Autodesk Inventor part; units mm, degrees
(part 2 of 2)
  line L877 (-195.7056, 63.0085) -> (-199.6927, 63.0085)
  line L878 (-201.2028, 81.1379) -> (-201.786, 81.1151)
  line L879 (-201.786, 81.1151) -> (-202.2096, 81.0461)
  line L880 (-202.2096, 81.0461) -> (-202.5152, 80.9103)
  line L881 (-202.5152, 80.9103) -> (-202.7369, 80.6784)
  line L882 (-202.7369, 80.6784) -> (-202.8877, 80.344)
  line L883 (-202.8877, 80.344) -> (-202.9805, 79.9076)
  line L884 (-202.9805, 79.9076) -> (-203.0286, 79.3151)
  line L885 (-203.0286, 79.3151) -> (-203.0444, 78.5051)
  line L886 (-203.0444, 78.5051) -> (-203.0056, 76.7655)
  line L887 (-203.0056, 76.7655) -> (-202.8887, 74.9256)
  line L888 (-202.8887, 74.9256) -> (-202.8067, 73.9341)
  line L889 (-202.8067, 73.9341) -> (-202.7609, 73.3636)
  line L890 (-202.7609, 73.3636) -> (-213.2957, 73.3636)
  line L891 (-213.2957, 73.3636) -> (-213.2957, 77.6862)
  line L892 (-213.2957, 77.6862) -> (-206.8037, 77.6862)
  line L893 (-206.8037, 77.6862) -> (-206.8797, 78.5292)
  line L894 (-206.8797, 78.5292) -> (-206.9367, 80.0385)
  line L895 (-206.9367, 80.0385) -> (-206.9556, 81.0341)
  line L896 (-206.9556, 81.0341) -> (-206.9328, 81.7671)
  line L897 (-206.9328, 81.7671) -> (-206.7505, 83.065)
  line L898 (-206.7505, 83.065) -> (-206.3859, 84.1386)
  line L899 (-206.3859, 84.1386) -> (-205.8393, 84.9882)
  line L900 (-205.8393, 84.9882) -> (-205.4975, 85.3288)
  line L901 (-205.4975, 85.3288) -> (-205.1474, 85.5896)
  line L902 (-205.1474, 85.5896) -> (-204.3364, 85.9849)
  line L903 (-204.3364, 85.9849) -> (-203.8754, 86.1199)
  line L904 (-203.8754, 86.1199) -> (-203.3727, 86.2211)
  line L905 (-203.3727, 86.2211) -> (-202.2283, 86.3369)
  line L906 (-202.2283, 86.3369) -> (-201.5863, 86.3515)
  line L907 (-201.5863, 86.3515) -> (-200.8617, 86.3369)
  line L908 (-200.8617, 86.3369) -> (-199.5953, 86.2211)
  line L909 (-199.5953, 86.2211) -> (-199.0535, 86.1199)
  line L910 (-199.0535, 86.1199) -> (-198.5613, 85.9849)
  line L911 (-198.5613, 85.9849) -> (-197.6925, 85.5896)
  line L912 (-197.6925, 85.5896) -> (-197.3156, 85.3288)
  line L913 (-197.3156, 85.3288) -> (-196.9763, 85.0191)
  line L914 (-196.9763, 85.0191) -> (-196.4069, 84.2201)
  line L915 (-196.4069, 84.2201) -> (-196.1771, 83.7308)
  line L916 (-196.1771, 83.7308) -> (-195.9838, 83.1808)
  line L917 (-195.9838, 83.1808) -> (-195.6961, 81.8842)
  line L918 (-195.6961, 81.8842) -> (-195.6018, 81.1379)
  line L919 (-195.6018, 81.1379) -> (-201.2028, 81.1379)
  line L920 (-213.2957, 78.7608) -> (-213.2957, 85.0491)
  line L921 (-213.2957, 85.0491) -> (-209.3327, 85.0491)
  line L922 (-209.3327, 85.0491) -> (-209.3327, 78.7608)
  line L923 (-209.3327, 78.7608) -> (-213.2957, 78.7608)
  line L924 (-195.5018, 78.8368) -> (-195.5468, 77.2848)
  line L925 (-195.5468, 77.2848) -> (-195.6816, 75.7527)
  line L926 (-195.6816, 75.7527) -> (-195.8774, 74.3455)
  line L927 (-195.8774, 74.3455) -> (-196.1132, 73.1599)
  line L928 (-196.1132, 73.1599) -> (-199.7725, 73.1599)
  line L929 (-199.7725, 73.1599) -> (-199.6257, 74.5822)
  line L930 (-199.6257, 74.5822) -> (-199.458, 77.139)
  line L931 (-199.458, 77.139) -> (-199.437, 78.2735)
  line L932 (-199.437, 78.2735) -> (-199.4501, 79.3223)
  line L933 (-199.4501, 79.3223) -> (-199.4889, 80.0633)
  line L934 (-199.4889, 80.0633) -> (-195.5259, 80.0633)
  line L935 (-195.5259, 80.0633) -> (-195.508, 79.5529)
  line L936 (-195.508, 79.5529) -> (-195.5018, 78.8368)
  line L937 (-204.5026, 98.0129) -> (-206.3415, 98.006)
  line L938 (-206.3415, 98.006) -> (-207.4151, 97.985)
  line L939 (-207.4151, 97.985) -> (-208.3299, 97.9081)
  line L940 (-208.3299, 97.9081) -> (-208.9251, 97.7812)
  line L941 (-208.9251, 97.7812) -> (-209.1228, 97.6795)
  line L942 (-209.1228, 97.6795) -> (-209.3963, 97.4039)
  line L943 (-209.3963, 97.4039) -> (-209.4725, 97.23)
  line L944 (-209.4725, 97.23) -> (-209.5595, 96.7365)
  line L945 (-209.5595, 96.7365) -> (-209.5884, 95.9915)
  line L946 (-209.5884, 95.9915) -> (-209.5753, 95.563)
  line L947 (-209.5753, 95.563) -> (-209.5365, 95.0447)
  line L948 (-209.5365, 95.0447) -> (-213.4755, 95.0447)
  line L949 (-213.4755, 95.0447) -> (-213.4934, 95.2375)
  line L950 (-213.4934, 95.2375) -> (-213.4995, 95.5041)
  line L951 (-213.4995, 95.5041) -> (-213.4995, 95.9915)
  line L952 (-213.4995, 95.9915) -> (-213.4714, 97.2571)
  line L953 (-213.4714, 97.2571) -> (-213.2477, 99.3286)
  line L954 (-213.2477, 99.3286) -> (-213.0521, 100.1343)
  line L955 (-213.0521, 100.1343) -> (-212.7923, 100.8152)
  line L956 (-212.7923, 100.8152) -> (-212.0572, 101.888)
  line L957 (-212.0572, 101.888) -> (-211.5819, 102.2797)
  line L958 (-211.5819, 102.2797) -> (-211.0734, 102.5689)
  line L959 (-211.0734, 102.5689) -> (-209.8351, 102.9644)
  line L960 (-209.8351, 102.9644) -> (-209.1049, 103.0708)
  line L961 (-209.1049, 103.0708) -> (-207.1873, 103.1876)
  line L962 (-207.1873, 103.1876) -> (-204.5026, 103.2265)
  line L963 (-204.5026, 103.2265) -> (-202.0716, 103.1976)
  line L964 (-202.0716, 103.1976) -> (-200.3079, 103.1107)
  line L965 (-200.3079, 103.1107) -> (-199.6211, 103.0327)
  line L966 (-199.6211, 103.0327) -> (-198.4186, 102.7451)
  line L967 (-198.4186, 102.7451) -> (-197.9029, 102.5354)
  line L968 (-197.9029, 102.5354) -> (-197.4, 102.2452)
  line L969 (-197.4, 102.2452) -> (-196.589, 101.4582)
  line L970 (-196.589, 101.4582) -> (-196.2809, 100.9614)
  line L971 (-196.2809, 100.9614) -> (-196.0303, 100.38)
  line L972 (-196.0303, 100.38) -> (-195.6788, 98.906)
  line L973 (-195.6788, 98.906) -> (-195.5778, 98.0129)
  line L974 (-195.5778, 98.0129) -> (-204.5026, 98.0129)
  line L975 (-195.5018, 95.9915) -> (-195.5297, 94.7356)
  line L976 (-195.5297, 94.7356) -> (-195.7537, 92.6702)
  line L977 (-195.7537, 92.6702) -> (-195.9493, 91.8607)
  line L978 (-195.9493, 91.8607) -> (-196.2106, 91.1744)
  line L979 (-196.2106, 91.1744) -> (-196.9574, 90.096)
  line L980 (-196.9574, 90.096) -> (-197.4435, 89.7032)
  line L981 (-197.4435, 89.7032) -> (-197.9518, 89.4141)
  line L982 (-197.9518, 89.4141) -> (-199.1783, 89.0165)
  line L983 (-199.1783, 89.0165) -> (-199.8965, 88.9083)
  line L984 (-199.8965, 88.9083) -> (-201.8031, 88.7945)
  line L985 (-201.8031, 88.7945) -> (-204.5026, 88.7564)
  line L986 (-204.5026, 88.7564) -> (-206.9305, 88.7846)
  line L987 (-206.9305, 88.7846) -> (-208.6935, 88.8684)
  line L988 (-208.6935, 88.8684) -> (-209.3815, 88.948)
  line L989 (-209.3815, 88.948) -> (-210.584, 89.2376)
  line L990 (-210.584, 89.2376) -> (-211.0984, 89.4476)
  line L991 (-211.0984, 89.4476) -> (-211.6029, 89.7375)
  line L992 (-211.6029, 89.7375) -> (-212.4139, 90.5224)
  line L993 (-212.4139, 90.5224) -> (-212.7205, 91.0177)
  line L994 (-212.7205, 91.0177) -> (-212.971, 91.6007)
  line L995 (-212.971, 91.6007) -> (-213.3226, 93.077)
  line L996 (-213.3226, 93.077) -> (-213.4236, 93.9701)
  line L997 (-213.4236, 93.9701) -> (-204.5026, 93.9701)
  line L998 (-204.5026, 93.9701) -> (-202.6788, 93.977)
  line L999 (-202.6788, 93.977) -> (-201.6103, 93.9979)
  line L1000 (-201.6103, 93.9979) -> (-200.7154, 94.0808)
  line L1001 (-200.7154, 94.0808) -> (-200.0762, 94.2257)
  line L1002 (-200.0762, 94.2257) -> (-199.8801, 94.3265)
  line L1003 (-199.8801, 94.3265) -> (-199.6065, 94.5942)
  line L1004 (-199.6065, 94.5942) -> (-199.5288, 94.7611)
  line L1005 (-199.5288, 94.7611) -> (-199.4419, 95.2485)
  line L1006 (-199.4419, 95.2485) -> (-199.413, 95.9915)
  line L1007 (-199.413, 95.9915) -> (-199.413, 96.5028)
  line L1008 (-199.413, 96.5028) -> (-199.426, 96.7015)
  line L1009 (-199.426, 96.7015) -> (-199.4649, 96.9383)
  line L1010 (-199.4649, 96.9383) -> (-195.5259, 96.9383)
  line L1011 (-195.5259, 96.9383) -> (-195.508, 96.7455)
  line L1012 (-195.508, 96.7455) -> (-195.5018, 96.4788)
  line L1013 (-195.5018, 96.4788) -> (-195.5018, 95.9915)
  constraints: 2028 end point, 6 parallel, 3 horizontal, 3 perpendicular
extrude "Cut1" cut sketch "Sketch3" against normal blind 2
fillet "R10 правые углы" radius 10 2 edges at (0, 120, 1) (266.0444, 120, 1)
equation "\"d0\" = Thickness"
equation "\"BendRadius\" = Thickness"
equation "\"BendReliefWidth\" = Thickness"
equation "\"BendReliefDepth\" = 0.5 * Thickness"
equation "\"CornerReliefSize\" = 4 * Thickness"
equation "\"MinimumRemnant\" = 2 * Thickness"
equation "\"TransitionRadius\" = BendRadius"
equation "\"JacobiRadiusSize\" = BendRadius"
equation "\"GapSize\" = Thickness"
equation "\"Thickness\" = 2"
body "Solid1"
